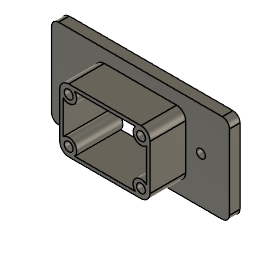
ToF_mount_front (Autodesk Fusion 360 design; units mm, degrees)
Autodesk Fusion 360 part; units mm, degrees
note: some values were not read from the file. Set by a fixed rule: which face or edge a step refers to.
sketch "Sketch1" plane through (0, 0, 0) normal (0, 1, 0) x (1, 0, 0)
  line L0 (-25, -12.5) -> (25, -12.5)
  line L1 (25, -12.5) -> (25, 12.5)
  line L2 (25, 12.5) -> (-25, 12.5)
  line L3 (-25, 12.5) -> (-25, -12.5)
  circle A0 centre (17, -0.5) radius 1.25
  circle A1 centre (-17, -0.5) radius 1.25
  dimension "d3" = 50
  dimension "d4" = 25
  dimension "d31" = 2.5
  dimension "d32" = 12
  dimension "d33" = 8
  dimension "d34" = 2.5
  dimension "d35" = 12
  dimension "d36" = 8
  constraint horizontal L0
  constraint vertical L1
  constraint horizontal L2
  constraint vertical L3
  measures "d3" distance of L0.start L0.end
  measures "d4" distance of L0.start L2.end
  measures "d31" diameter of A0
  measures "d32" distance of L0 A0.centre
  measures "d33" distance of L1 A0.centre
  measures "d34" diameter of A1
  measures "d35" distance of L0 A1.centre
  measures "d36" distance of L3 A1.centre
sketch "Sketch2" plane through (0, 0, 0) normal (0, 1, 0) x (1, 0, 0)
  line L0 (10.16, 8.89) -> (-10.16, 8.89)
  line L1 (-11.9561, 8.1461) -> (11.9561, -8.1461) construction
  line L2 (12.7, -6.35) -> (12.7, 6.35)
  arc A0 (-10.16, 8.89) -> (-12.7, 6.35) centre (-10.16, 6.35) ccw
  line L3 (-10.16, -8.89) -> (10.16, -8.89)
  arc A1 (12.7, 6.35) -> (10.16, 8.89) centre (10.16, 6.35) ccw
  arc A2 (-12.7, -6.35) -> (-10.16, -8.89) centre (-10.16, -6.35) ccw
  circle A3 centre (10.16, -6.35) radius 1.25
  arc A4 (10.16, -8.89) -> (12.7, -6.35) centre (10.16, -6.35) ccw
  circle A5 centre (10.16, 6.35) radius 1.25
  line L4 (-12.7, 6.35) -> (-12.7, -6.35)
  circle A6 centre (-10.16, 6.35) radius 1.25
  circle A7 centre (-10.16, -6.35) radius 1.25
  constraint midpoint L1.start A0
  constraint midpoint L1.end A4
extrude "Extrude1" add sketch "Sketch1" along normal blind 3 contours L0 L1 L2 L3 | A0 | A1
extrude "Extrude2" add sketch "Sketch2" against normal blind 2 thin wall 1 inside
extrude "Extrude3" cut sketch "Sketch2" along normal blind 10 contours A3 | A5 | A6 | A7
sketch "Sketch3" plane through (0, 0, 0) normal (0, 1, 0) x (1, 0, 0)
extrude "Extrude8" cut sketch "Sketch1" along normal blind 11 contours A0 | A1
move_face "OffsetFaces1" offset -17 1 faces at (-2.7534, 0, -1.7148)
extrude "Extrude9" add 1 faces at (2.8399, -2, 8.5567) along direction (0, -1, 0) blind 8
fillet "Fillet4" radius 2 1 edges at (25, 1.5, 12.5)
fillet "Fillet5" radius 2 1 edges at (-25, 1.5, 12.5)
fillet "Fillet6" radius 2 1 edges at (-25, 1.5, -12.5)
fillet "Fillet7" radius 2 1 edges at (25, 1.5, -12.5)
